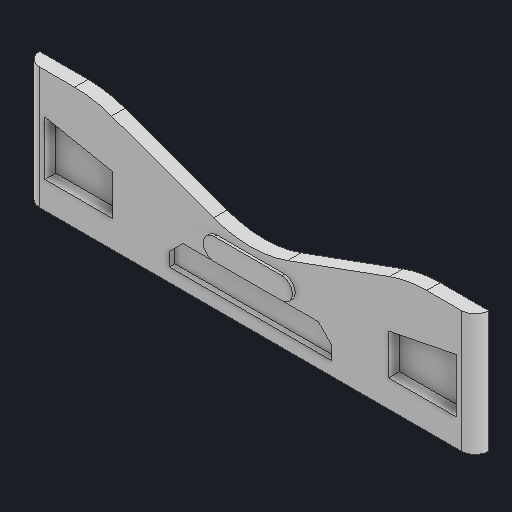
# Autodesk Inventor part: 7_3_2_part_choc
Saved by Autodesk Inventor 2026 (Build 300175000, 175)
## iProperties
Created: 2025-06-21
Part Number: 7_3_2_part_choc
Material: Generic
Document SubType Name: Modeling
Designer: remg9
Density: 1 g/cm^3
Appearance: Default
Author: remg9
Autodesk Inventor part; units mm, degrees
ref_plane "YZ Plane" through (0, 0, 0) normal (1, 0, 0) x (0, 1, 0)
ref_plane "XZ Plane" through (0, 0, 0) normal (0, 1, 0) x (-1, 0, 0)
ref_plane "XY Plane" through (0, 0, 0) normal (0, 0, 1) x (1, 0, 0)
sketch "Sketch1" plane through (0, 0, 0) normal (0, 0, 1) x (1, 0, 0)
  line L0 (0, 0) -> (166, 0)
  line L1 (166, 0) -> (166, 45)
  line L2 (166, 45) -> (141, 45)
  line L3 (141, 45) -> (83, 23.8897)
  line L4 (83, 23.8897) -> (25, 45)
  line L5 (25, 45) -> (0, 45)
  line L6 (0, 45) -> (0, 0)
  line L7 (83, 23.8897) -> (83, 0) construction
  point P0 (54, 34.4449)
  point P1 (153.5, 45)
  dimension "d0" = 166
  dimension "d1" = 25
  dimension "d2" = 25
  dimension "d4" = 20
  dimension "d5" = 20
  dimension "d6" = 45
  dimension "d34" = 83
  constraints: 16 end point, 3 midpoint, 3 perpendicular, 2 point on line, 1 horizontal, 1 vertical
  measures "d0" distance of L0.start L0.end
  measures "d1" distance of L1.end L2.end
  measures "d2" distance of L4.end L5.end
  measures "d4" angle of L5 L4
  measures "d5" angle of L2 L3
  measures "d6" distance from line of L0 point (153.5, 45)
  measures "d34" distance between parallel lines of L6 L7
extrude "Extrusion1" add sketch "Sketch1" along normal blind 5
sketch "Sketch2" plane through (0, 0, 5) normal (0, 0, 1) x (1, 0, 0)
  line L0 (83, 23.8897) -> (83, 0) construction
  line L1 (0, 0) -> (166, 0) projected
  line L2 (7, 30) -> (32, 25)
  line L3 (32, 25) -> (32, 10)
  line L4 (32, 10) -> (7, 10)
  line L5 (7, 10) -> (7, 30)
  line L6 (0, 45) -> (0, 0) projected
  line L7 (159, 30) -> (134, 25)
  line L8 (134, 25) -> (134, 10)
  line L9 (134, 10) -> (159, 10)
  line L10 (159, 10) -> (159, 30)
  line L11 (166, 45) -> (166, 0)
  dimension "d9" = 20
  dimension "d10" = 7
  dimension "d11" = 10
  dimension "d13" = 15
  dimension "d14" = 25
  constraints: 20 end point, 5 symmetric about line, 2 vertical, 1 coincident, 1 midpoint
  measures "d9" distance of L4.end L2.start
  measures "d10" distance between parallel lines of L6 L5
  measures "d11" distance between parallel lines of L1 L4
  measures "d13" distance of L2.end L3.end
  measures "d14" distance of L3.end L4.end
extrude "Extrusion2" cut sketch "Sketch2" against normal blind 4
sketch "Sketch3" plane through (0, 0, 5) normal (0, 0, 1) x (1, 0, 0)
  line L0 (58, 15) -> (108, 15)
  line L1 (113, 10) -> (113, 5)
  line L2 (113, 5) -> (53, 5)
  line L3 (53, 5) -> (53, 10)
  line L4 (0, 0) -> (166, 0) projected
  line L5 (83, 15) -> (83, 23.8897) construction
  line L6 (58, 15) -> (53, 10)
  line L7 (108, 15) -> (113, 10)
  point P0 (53, 15)
  point P1 (113, 15)
  dimension "d17" = 5
  dimension "d18" = 5
  dimension "d19" = 5
  dimension "d20" = 5
  dimension "d21" = 5
  dimension "d22" = 10
  dimension "d23" = 60
  constraints: 14 end point, 4 point on line, 2 parallel, 1 coincident, 1 horizontal, 1 midpoint, 1 perpendicular, 1 vertical
  measures "d17" distance between parallel lines of L4 L2
  measures "d18" distance of L0.start point (53, 15)
  measures "d19" distance of L3.end point (53, 15)
  measures "d20" distance of L0.end point (113, 15)
  measures "d21" distance of L1.start point (113, 15)
  measures "d22" distance between parallel lines of L2 L0
  measures "d23" distance of L1.end L2.end
extrude "Extrusion3" cut sketch "Sketch3" against normal blind 2
sketch "Sketch4" plane through (0, 0, 5) normal (0, 0, 1) x (1, 0, 0)
  line L0 (70.5, 20) -> (95.5, 20) construction
  line L1 (70.5, 16) -> (95.5, 16)
  line L2 (95.5, 24) -> (70.5, 24)
  arc A0 (70.5, 24) -> (70.5, 16) centre (70.5, 20) ccw
  arc A1 (95.5, 16) -> (95.5, 24) centre (95.5, 20) ccw
  line L3 (58, 15) -> (108, 15) projected
  line L4 (83, 20) -> (83, 23.8897) construction
  point P0 (0, 0)
  dimension "d26" = 8
  dimension "d27" = 1
  dimension "d28" = 25
  constraints: 10 end point, 4 point on circle, 4 tangent, 2 centre point, 1 coincident, 1 horizontal, 1 midpoint, 1 parallel, 1 vertical
  measures "d26" distance between parallel lines of L1 L2
  measures "d27" distance between parallel lines of L3 L1
  measures "d28" distance of L0.start L0.end
extrude "Extrusion4" add sketch "Sketch4" along normal blind 1
fillet "Fillet1" radius 40 3 edges at (83, 23.8897, 2.5) (25, 45, 2.5) (141, 45, 2.5)
fillet "Fillet4" radius 5 2 edges at (166, 22.5, 5) (0, 22.5, 5)
equation "\"d19\" = d18"
equation "\"d20\" = d18"
equation "\"d21\" = d20"
body "Solid1"
